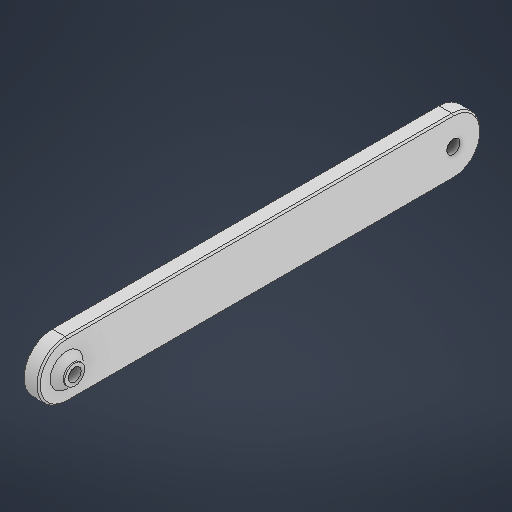
# Autodesk Inventor part: pendulum_2
Saved by Autodesk Inventor 2027.1 (Build 311270010, 270A)
## iProperties
Created: 2026-10-10
Part Number: pendulum_2
Material: Generic
Document SubType Name: Modeling
Designer: lucao
Density: 0.341059 g/cm^3
Appearance: Default
Mass: 31.62 g
Surface Area: 244.844 cm^2
Volume: 92.7112 cm^3
Author: lucao
## iProperties of the stored document pendulum_2_3DPrint.ipt
Created: 2026-10-14
Part Number: pendulum_2_3DPrint
Material: Generic
Document SubType Name: Modeling
Designer: lucao
Density: 1 g/cm^3
Appearance: Default
Author: lucao
Autodesk Inventor part; units mm, degrees
ref_plane "YZ Plane" through (0, 0, 0) normal (1, 0, 0) x (0, 1, 0)
ref_plane "XZ Plane" through (0, 0, 0) normal (0, 1, 0) x (-1, 0, 0)
ref_plane "XY Plane" through (0, 0, 0) normal (0, 0, 1) x (1, 0, 0)
sketch "Sketch1" plane through (0, 0, 0) normal (1, 0, 0) x (0, 1, 0)
  circle A0 centre (0, 0) radius 4.025
  circle A1 centre (0, 0) radius 17.5
  circle A2 centre (0, -240) radius 17.5
  line L0 (17.5, 0) -> (17.5, -240)
  line L1 (-17.5, -240) -> (-17.5, 0)
  circle A3 centre (0, -240) radius 4.15
  dimension "d0" = 8.05
  dimension "d1" = 35
  dimension "d2" = 35
  dimension "d3" = 240
  dimension "d4" = 8.3
  constraints: 4 centre point, 4 end point, 4 point on circle, 4 tangent, 3 coincident, 1 vertical alignment
  measures "d0" diameter of A0
  measures "d1" diameter of A1
  measures "d2" diameter of A2
  measures "d3" distance of point (0, 0) A2.centre
  measures "d4" diameter of A3
extrude "Extrusion1" add sketch "Sketch1" along normal blind 10
sketch "Sketch2" plane through (10, 0, 0) normal (1, 0, 0) x (0, 0, -1)
  circle A0 centre (0, 0) radius 4.025 projected
  circle A1 centre (0, 0) radius 6.2
  dimension "d7" = 12.4
  constraints: 1 centre point, 1 coincident
  measures "d7" diameter of A1
extrude "Extrusion2" add sketch "Sketch2" along normal blind 5
chamfer "Chamfer1" distance 4 angle 45 1 edges at (10, 0, 6.2)
chamfer "Chamfer2" distance 1 angle 45 8 edges at (10, 0, 17.5) (10, -17.5, -120) (10, 0, -257.5) (10, 17.5, -120) (0, 0, 17.5) (0, -17.5, -120) (0, 0, -257.5) (0, 17.5, -120)
body "Solid1"
